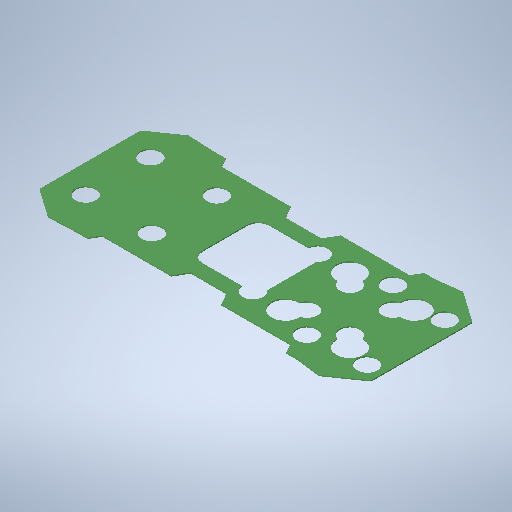
# Autodesk Inventor part: Shock Absorber
Saved by Autodesk Inventor 2025.2 (Build 292293000, 293)
## iProperties
Created: 2026-05-26
Part Number: Shock Absorber
Material: Generic
Document SubType Name: Modeling
Designer: crazi
Density: 1 g/cm^3
Appearance: Smooth - Dark Forest Green
Author: crazi
Autodesk Inventor part; units mm, degrees
ref_plane "YZ Plane" through (0, 0, 0) normal (1, 0, 0) x (0, 1, 0)
ref_plane "XZ Plane" through (0, 0, 0) normal (0, 1, 0) x (-1, 0, 0)
ref_plane "XY Plane" through (0, 0, 0) normal (0, 0, 1) x (1, 0, 0)
sketch "Sketch1" plane through (0, 0, 0) normal (0, 1, 0) x (-1, 0, 0)
  line L0 (78.7128, 25.3433) -> (78.6878, 25.3433)
  line L1 (-81.2623, 25.3433) -> (-81.2622, 25.3433)
  line L2 (-81.2623, -24.6567) -> (-81.2622, -24.6567)
  line L3 (13.0887, -10.1567) -> (13.0887, 10.8433)
  arc A0 (13.0887, 10.8433) -> (8.0887, 15.8433) centre (8.0887, 10.8433) ccw
  line L4 (8.0887, 15.8433) -> (-10.176, 15.8433)
  arc A1 (-17.833, 11.7242) -> (-17.9113, 10.8433) centre (-12.9113, 10.8433) ccw
  line L5 (-17.9113, 10.8433) -> (-17.9113, -10.1567)
  arc A2 (-17.9113, -10.1567) -> (-17.833, -11.0377) centre (-12.9113, -10.1567) ccw
  line L6 (-10.176, -15.1567) -> (8.0887, -15.1567)
  arc A3 (8.0887, -15.1567) -> (13.0887, -10.1567) centre (8.0887, -10.1567) ccw
  circle A4 centre (62.7128, 15.3433) radius 4.75
  circle A5 centre (62.7128, -14.6567) radius 4.75
  circle A6 centre (31.904, 15.4693) radius 4.75
  circle A7 centre (31.904, -14.7827) radius 4.75
  arc A8 (-17.833, -11.0377) -> (-10.176, -15.1567) centre (-14.9113, -14.7827) ccw
  arc A9 (-10.176, 15.8433) -> (-17.833, 11.7242) centre (-14.9113, 15.4693) ccw
  arc A10 (-30.3524, 9.0051) -> (-36.2457, 14.8985) centre (-29.9111, 15.3398) ccw
  arc A11 (-36.2457, 14.8985) -> (-30.3524, 9.0051) centre (-34.911, 10.3398) ccw
  arc A12 (-30.3524, -8.3186) -> (-36.2457, -14.2119) centre (-34.911, -9.6533) ccw
  arc A13 (-36.2457, -14.2119) -> (-30.3524, -8.3186) centre (-29.9111, -14.6533) ccw
  circle A14 centre (-44.9111, -19.6533) radius 4.75
  circle A15 centre (-44.9111, 20.3398) radius 4.75
  arc A16 (-59.4697, 9.0051) -> (-53.5764, 14.8985) centre (-54.9111, 10.3398) ccw
  arc A17 (-53.5764, 14.8985) -> (-59.4697, 9.0051) centre (-59.9111, 15.3398) ccw
  circle A18 centre (-70.9113, 18.3398) radius 4.75
  arc A19 (-53.5764, -14.2119) -> (-59.4697, -8.3186) centre (-54.9111, -9.6533) ccw
  arc A20 (-59.4697, -8.3186) -> (-53.5764, -14.2119) centre (-59.9111, -14.6533) ccw
  circle A21 centre (-70.9113, -17.6533) radius 4.75
  line L7 (62.6856, 32.8858) -> (75.7128, 23.7641)
  line L8 (75.7128, 23.7641) -> (75.7128, -23.0776)
  line L9 (75.7128, -23.0776) -> (62.6856, -32.1993)
  line L10 (50.094, 32.3433) -> (44.8261, 32.3433)
  line L11 (44.8261, 32.3433) -> (42.3261, 28.0131)
  line L12 (42.3261, 28.0131) -> (10.3261, 28.0131)
  line L13 (10.3261, 28.0131) -> (7.0526, 22.3433)
  line L14 (7.0526, 22.3433) -> (-9.627, 22.3433)
  line L15 (-9.627, 22.3433) -> (-12.9005, 28.0131)
  line L16 (-12.9005, 28.0131) -> (-44.9005, 28.0131)
  line L17 (-44.9005, 28.0131) -> (-47.4005, 32.3433)
  line L18 (-47.4005, 32.3433) -> (-52.6684, 32.3433)
  line L19 (50.094, -31.6567) -> (44.8261, -31.6567)
  line L20 (44.8261, -31.6567) -> (42.3261, -27.3266)
  line L21 (42.3261, -27.3266) -> (10.3261, -27.3266)
  line L22 (10.3261, -27.3266) -> (7.0526, -21.6567)
  line L23 (7.0526, -21.6567) -> (-9.627, -21.6567)
  line L24 (-9.627, -21.6567) -> (-12.9005, -27.3266)
  line L25 (-12.9005, -27.3266) -> (-44.9005, -27.3266)
  line L26 (-44.9005, -27.3266) -> (-47.4005, -31.6567)
  line L27 (-47.4005, -31.6567) -> (-52.6684, -31.6567)
  line L28 (-74.1215, 30.3433) -> (-71.1215, 30.3433) construction
  line L29 (-74.1215, -29.6567) -> (-71.1215, -29.6567) construction
  line L30 (-78.2622, 23.7816) -> (-78.2622, -23.0951)
  line L31 (-78.2622, 23.7816) -> (-63.9811, 33.7813)
  line L32 (-78.2622, -23.0951) -> (-63.9811, -33.0948)
  line L33 (-63.9811, 33.7813) -> (-52.6684, 32.3433)
  line L34 (-63.9811, -33.0948) -> (-52.6684, -31.6567)
  line L35 (62.6856, -32.1993) -> (50.094, -31.6567)
  line L36 (62.6856, 32.8858) -> (50.094, 32.3433)
  point P0 (0, 0)
  dimension "d29" = 17.434
  dimension "d30" = 17.434
  constraints: 74 end point, 28 point on circle, 22 centre point, 2 horizontal, 1 vertical
  measures "d29" distance of L30.start L31.end
  measures "d30" distance of L30.end L32.end
extrude "Extrusion1" add sketch "Sketch1" along normal blind 0.5
body "Solid1"
